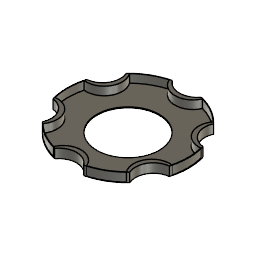
Steering spacer (Autodesk Fusion 360 design; units mm, degrees)
Autodesk Fusion 360 part; units mm, degrees
sketch "Skizze1" plane through (0, 0, 0) normal (0, 0, 1) x (1, 0, 0)
  arc A0 (-8, 27.8747) -> (8, 27.8747) centre (0, 31.304) ccw
  arc A1 (-28.1402, 7.0092) -> (-20.1402, 20.8656) centre (-27.1101, 15.652) ccw
  arc A2 (-20.1402, -20.8656) -> (-28.1402, -7.0092) centre (-27.1101, -15.652) ccw
  arc A3 (8, -27.8747) -> (-8, -27.8747) centre (0, -31.304) ccw
  arc A4 (28.1402, -7.0092) -> (20.1402, -20.8656) centre (27.1101, -15.652) ccw
  arc A5 (20.1402, 20.8656) -> (28.1402, 7.0092) centre (27.1101, 15.652) ccw
  arc A6 (20.1402, 20.8656) -> (8, 27.8747) centre (0, 0) ccw
  arc A7 (28.1402, -7.0092) -> (28.1402, 7.0092) centre (0, 0) ccw
  arc A8 (8, -27.8747) -> (20.1402, -20.8656) centre (0, 0) ccw
  arc A9 (-20.1402, -20.8656) -> (-8, -27.8747) centre (0, 0) ccw
  arc A10 (-8, 27.8747) -> (-20.1402, 20.8656) centre (0, 0) ccw
  arc A11 (-28.1402, 7.0092) -> (-28.1402, -7.0092) centre (0, 0) ccw
  circle A12 centre (0, 0) radius 29.2
  arc A13 (-7, 28.3485) -> (7, 28.3485) centre (0, 33.3576) ccw
  arc A14 (-28.0506, 8.1121) -> (-21.0506, 20.2365) centre (-28.8885, 16.6788) ccw
  arc A15 (-21.0506, -20.2365) -> (-28.0506, -8.1121) centre (-28.8885, -16.6788) ccw
  arc A16 (7, -28.3485) -> (-7, -28.3485) centre (0, -33.3576) ccw
  arc A17 (28.0506, -8.1121) -> (21.0506, -20.2365) centre (28.8885, -16.6788) ccw
  arc A18 (21.0506, 20.2365) -> (28.0506, 8.1121) centre (28.8885, 16.6788) ccw
  circle A19 centre (0, 0) radius 15
  point P0 (0, 22.6)
  point P1 (0, 24.75)
  point P2 (-7, 28.3485)
  point P3 (7, 28.3485)
  dimension "d1" = 58
  dimension "d2" = 22.6
  dimension "d3" = 16
  dimension "d5" = 360
  dimension "d6" = 58.4
  dimension "d7" = 24.75
  dimension "d8" = 14
  dimension "d10" = 360
  dimension "d13" = 30
  constraint coincident A6.centre A7.centre
  constraint vertical A6.centre A0.centre
  constraint midpoint A0 P0
  constraint concentric A6 A10
  constraint concentric A7 A10
  constraint concentric A8 A10
  constraint concentric A9 A10
  constraint concentric A10 A11
  constraint concentric A11 A12
  constraint coincident A12 P2
  constraint vertical A0.centre A13.centre
  constraint coincident A12 P3
  constraint midpoint A13 P1
  constraint coincident P2 A13.start
  constraint coincident P3 A13.end
  measures "d1" diameter of A10
  measures "d2" distance of A6.centre P0
  measures "d3" distance of A0.start A0.end
  measures "d6" diameter of A12
  measures "d7" distance of A6.centre P1
  measures "d8" distance of P2 P3
  measures "d13" diameter of A19
extrude "Extrusion1" add sketch "Skizze1" along normal blind 4 contours A12 A13 A14 A15 A16 A17 A18
extrude "Extrusion2" add sketch "Skizze1" against normal blind 0.4 contours A0 A1 A2 A3 A4 A5 A6 A7 A8 A9 A10 A11 | A12 A13 A14 A15 A16 A17 A18
equation "d2 = ( 45.2 / 2 ) * 1 mm"
equation "d7 = ( 49.5 / 2 ) * 1 mm"
